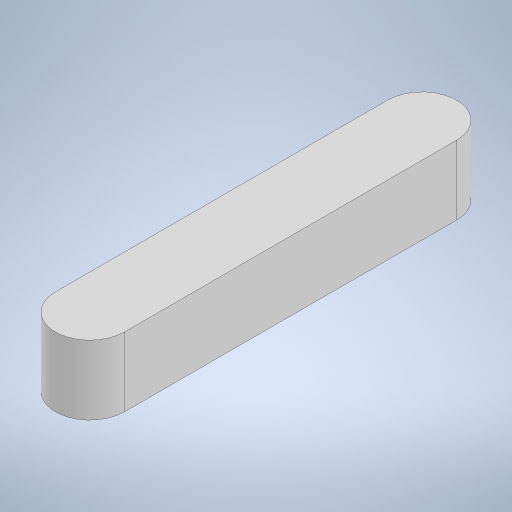
# Autodesk Inventor part: KeyG2
Saved by Autodesk Inventor 2023 (Build 270158000, 158)
## iProperties
Created: 2024-05-11
Part Number: KeyG2
Material: Generic
Document SubType Name: Modeling
Designer: BenFr
Density: 1 g/cm^3
Appearance: Default
Author: BenFr
Autodesk Inventor part; units mm, degrees
ref_plane "YZ Plane" through (0, 0, 0) normal (1, 0, 0) x (0, 1, 0)
ref_plane "XZ Plane" through (0, 0, 0) normal (0, 1, 0) x (-1, 0, 0)
ref_plane "XY Plane" through (0, 0, 0) normal (0, 0, 1) x (1, 0, 0)
sketch "Sketch1" plane through (0, 0, 0) normal (0, 1, 0) x (-1, 0, 0)
  line L0 (-3, 17.4) -> (3, 17.4)
  line L1 (3, 17.4) -> (3, -17.4)
  line L2 (3, -17.4) -> (-3, -17.4)
  line L3 (-3, -17.4) -> (-3, 17.4)
  line L4 (-3, 17.4) -> (3, -17.4) construction
  line L5 (3, 17.4) -> (-3, -17.4) construction
  point P0 (0, 0)
  dimension "d0" = 6
  dimension "d1" = 34.8
  constraints: 12 end point, 2 midpoint, 2 parallel, 1 horizontal, 1 perpendicular
  measures "d0" distance of L1.end L2.end
  measures "d1" distance of L0.end L1.end
extrude "Extrusion1" add sketch "Sketch1" along normal blind 6
fillet "Fillet1" radius 3 4 edges at (-3, 3, 17.4) (3, 3, 17.4) (3, 3, -17.4) (-3, 3, -17.4)
body "Solid1"
